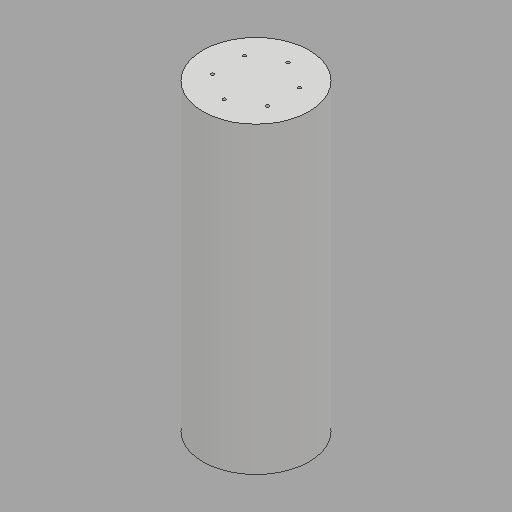
# Autodesk Inventor part: BT016_thutrn22_26
Saved by Autodesk Inventor 2025.3 (Build 293356000, 356)
## iProperties
Company: HTBLA Kaindorf
RuleStatus: InUse
Created: 2026-08-13
Part Number: BT016_thutrn22_26
Project: Biegeroboter
Material: Generisch
Description: roboter_flansch
Document SubType Name: Modeling
Designer: thutrn22
Density: 1 g/cm^3
Appearance: Vorgabe
Mass: 95691.7 g
Surface Area: 14888.6 cm^2
Volume: 95691.7 cm^3
AfterDocNew0: iProperties-Editor_aufrufen
Author: trist
Keywords: 2026
Autodesk Inventor part; units mm, degrees
ref_plane "YZ Plane" through (0, 0, 0) normal (1, 0, 0) x (0, 1, 0)
ref_plane "XZ Plane" through (0, 0, 0) normal (0, 1, 0) x (-1, 0, 0)
ref_plane "XY Plane" through (0, 0, 0) normal (0, 0, 1) x (1, 0, 0)
sketch "Skizze3" plane through (0, 0, 0) normal (0, 0, 1) x (1, 0, 0)
  line L0 (0, -245) -> (0, 245) projected
  line L1 (-245, 0) -> (245, 0) projected
  circle A0 centre (0, 0) radius 175
  circle A1 centre (0, 0) radius 105
  point P0 (-105, 0)
  point P1 (-52.5, -90.9327)
  point P2 (52.5, -90.9327)
  point P3 (105, 0)
  point P4 (52.5, 90.9327)
  point P5 (-52.5, 90.9327)
  dimension "d6" = 350
  dimension "d7" = 105
  dimension "d8" = 210
  dimension "d11" = 360
  constraints: 2 centre point, 2 coincident, 1 point on line, 7 other
  measures "d6" diameter of A0
  measures "d7" distance from line of point (-105, 0) L0
  measures "d8" diameter of A1
extrude "Extrusion3" add sketch "Skizze3" along normal blind 1000
hole "Bohrung1" at (-105, 0, 0) at (-52.5, -90.9327, 0) at (52.5, -90.9327, 0) at (105, 0, 0) at (52.5, 90.9327, 0) at (-52.5, 90.9327, 0) direction (0, 0, 1) diameter 10.5 end through all
